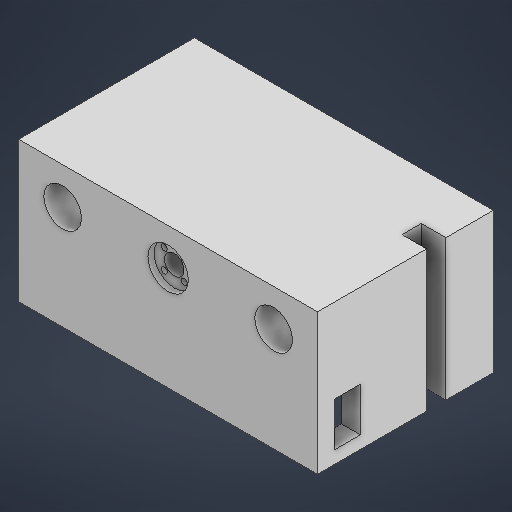
# Autodesk Inventor part: NutHousing
Saved by Autodesk Inventor 2027.1 (Build 311270010, 270A)
## iProperties
Created: 2026-09-20
Part Number: NutHousing
Material: Generic
Document SubType Name: Modeling
Designer: khaar
Density: 1 g/cm^3
Appearance: Default
Author: khaar
Autodesk Inventor part; units mm, degrees
ref_plane "YZ Plane" through (0, 0, 0) normal (1, 0, 0) x (0, 1, 0)
ref_plane "XZ Plane" through (0, 0, 0) normal (0, 1, 0) x (-1, 0, 0)
ref_plane "XY Plane" through (0, 0, 0) normal (0, 0, 1) x (1, 0, 0)
sketch "Sketch4" plane through (0, 0, 0) normal (0, 0, 1) x (1, 0, 0)
  line L0 (-85, 21) -> (85, 21)
  line L1 (85, 21) -> (85, -21)
  line L2 (85, -21) -> (-85, -21)
  line L3 (-85, -21) -> (-85, 21)
  line L4 (-85, 21) -> (85, -21) construction
  line L5 (85, 21) -> (-85, -21) construction
  point P0 (0, 0)
  dimension "d5" = 170
  dimension "d6" = 42
  constraints: 12 end point, 2 midpoint, 2 parallel, 1 horizontal, 1 perpendicular
  measures "d5" distance of L0.start L0.end
  measures "d6" distance of L2.end L0.start
extrude "Extrusion2" add sketch "Sketch4" along normal mid plane 100
sketch "Sketch5" plane through (0, 0, 50) normal (0, 0, 1) x (1, 0, 0)
  circle A0 centre (0, 0) radius 5.6
  dimension "d9" = 11.2
  constraints: 1 centre point, 1 coincident
  measures "d9" diameter of A0
extrude "Extrusion3" cut sketch "Sketch5" against normal blind 50
sketch "Sketch7" plane through (0, 0, 50) normal (0, 0, 1) x (1, 0, 0)
  circle A0 centre (0, 0) radius 11.5
  dimension "d21" = 23
  constraints: 1 centre point, 1 coincident
  measures "d21" diameter of A0
extrude "Extrusion5" cut sketch "Sketch7" against normal blind 3.5
sketch "Sketch8" plane through (0, 0, 46.5) normal (0, 0, 1) x (1, 0, 0)
  circle A0 centre (0, 0) radius 8
  circle A1 centre (5.6569, 5.6569) radius 1.75
  line L0 (0, 8) -> (0, 0)
  line L1 (0, 0) -> (5.6569, 5.6569)
  circle A2 centre (-5.6569, 5.6569) radius 1.75
  circle A3 centre (-5.6569, -5.6569) radius 1.75
  circle A4 centre (5.6569, -5.6569) radius 1.75
  dimension "d24" = 16
  dimension "d25" = 3.5
  dimension "d26" = 45
  dimension "d29" = 360
  constraints: 5 centre point, 4 end point, 2 point on circle, 1 coincident, 1 vertical, 9 other
  measures "d24" diameter of A0
  measures "d25" diameter of A1
  measures "d26" angle of L1 L0
extrude "Extrusion6" cut sketch "Sketch8" against normal blind 3.5 contours A1 L1 A0 | A0 A1 | A4 A0 | A0 A4 | L1 A1 A0 | A3 A0 | A0 A3 | A2 A0 | A0 A2
sketch "Sketch11" plane through (0, 0, -50) normal (0, 0, -1) x (-1, 0, 0)
  circle A0 centre (60, 0) radius 10.7
  circle A1 centre (-60, 0) radius 10.7
  line L0 (85, -21) -> (85, 21) projected
  line L1 (-85, 21) -> (-85, -21) projected
  point P0 (0, 0)
  dimension "d38" = 21.4
  dimension "d39" = 21.4
  dimension "d40" = 25
  dimension "d41" = 25
  constraints: 2 centre point
  measures "d38" diameter of A0
  measures "d39" diameter of A1
  measures "d40" distance from line of L0 A0.centre
  measures "d41" distance from line of L1 A1.centre
extrude "Extrusion9" cut sketch "Sketch11" against normal blind 100
sketch "Sketch12" plane through (-85, -21, 50) normal (0, -1, 0) x (1, 0, 0)
  line L0 (0, -100) -> (0, 0) projected
  line L1 (170, -100) -> (170, 0) projected
  line L2 (0, -100) -> (170, -100)
  line L3 (170, -100) -> (170, 0)
  line L4 (170, 0) -> (0, 0)
  line L5 (0, 0) -> (0, -100)
  point P0 (85, -50)
  point P1 (170, -100)
  constraints: 8 end point, 2 parallel, 1 horizontal, 1 perpendicular
extrude "Extrusion10" add sketch "Sketch12" along normal blind 38
sketch "Sketch13" plane through (-85, -59, 50) normal (0, -1, 0) x (1, 0, 0)
  line L0 (9.1942, -91.3616) -> (159.1942, -91.3616)
  line L1 (159.1942, -91.3616) -> (159.1942, -6.3616)
  line L2 (159.1942, -6.3616) -> (9.1942, -6.3616)
  line L3 (9.1942, -6.3616) -> (9.1942, -91.3616)
  point P0 (85, -50)
  dimension "d48" = 85
  dimension "d49" = 150
  constraints: 8 end point, 2 parallel, 1 horizontal, 1 perpendicular
  measures "d48" distance of L2.end L0.start
  measures "d49" distance of L0.start L0.end
extrude "Extrusion11" cut sketch "Sketch13" against normal blind 40
sketch "Sketch14" plane through (85, 21, 50) normal (1, 0, 0) x (0, 0, -1)
  line L0 (24.4088, -47.8159) -> (9.4088, -47.8159)
  line L1 (9.4088, -47.8159) -> (9.4088, -72.8159)
  line L2 (9.4088, -72.8159) -> (24.4088, -72.8159)
  line L3 (24.4088, -72.8159) -> (24.4088, -47.8159)
  point P0 (50, -21)
  dimension "d50" = 25
  dimension "d51" = 15
  constraints: 8 end point, 2 parallel, 1 horizontal, 1 perpendicular
  measures "d50" distance of L2.end L0.start
  measures "d51" distance of L1.end L2.end
extrude "Extrusion12" cut sketch "Sketch14" against normal blind 12
sketch "Sketch15" plane through (85, 21, 50) normal (1, 0, 0) x (0, 0, -1)
  line L0 (100, 0) -> (0, 0) projected
  line L1 (73.0574, 0) -> (62.0574, 0)
  line L2 (62.0574, 0) -> (62.0574, -80)
  line L3 (62.0574, -80) -> (73.0574, -80)
  line L4 (73.0574, -80) -> (73.0574, 0)
  point P0 (50, -21)
  dimension "d56" = 11
  constraints: 8 end point, 2 parallel, 1 horizontal, 1 perpendicular, 1 point on line
  measures "d56" distance of L2.end L3.end
extrude "Extrusion13" cut sketch "Sketch15" against normal blind 14
sketch "Sketch16" plane through (0, 0, -50) normal (0, 0, -1) x (-1, 0, 0)
  circle A0 centre (0, 0) radius 7.7
  dimension "d57" = 15.4
  constraints: 1 centre point, 1 coincident
  measures "d57" diameter of A0
extrude "Extrusion14" cut sketch "Sketch16" against normal blind 50
body "Solid2"
